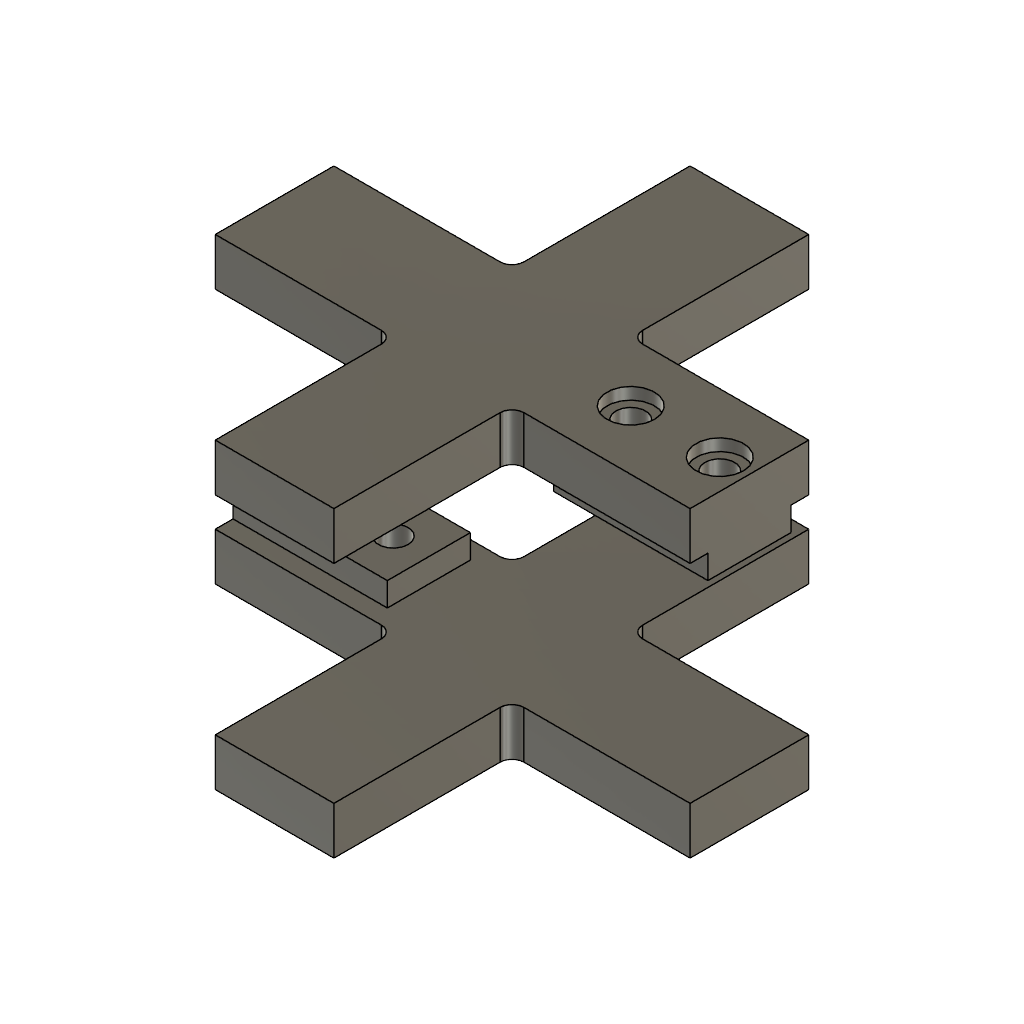
Sostegno_Sensore (Autodesk Fusion 360 design; units mm, degrees)
part number: 2026-10-16-15-58-05-429
Autodesk Fusion 360 part; units mm, degrees
sketch "Schizzo1" plane through (0, 0, 0) normal (0, 0, 1) x (1, 0, 0)
  line L0 (40, 10) -> (40, -10)
  line L1 (-40, -10) -> (-40, 10)
  line L2 (-10, 40) -> (10, 40)
  line L3 (10, -40) -> (-10, -40)
  line L4 (-10, -40) -> (-10, -12)
  line L5 (-10, 12) -> (-10, 40)
  line L6 (10, 40) -> (10, 12)
  line L7 (10, -12) -> (10, -40)
  line L8 (-40, 10) -> (-12, 10)
  line L9 (12, 10) -> (40, 10)
  line L10 (40, -10) -> (12, -10)
  line L11 (-12, -10) -> (-40, -10)
  arc A0 (-12, 10) -> (-10, 12) centre (-12, 12) ccw
  arc A1 (10, 12) -> (12, 10) centre (12, 12) ccw
  arc A2 (12, -10) -> (10, -12) centre (12, -12) ccw
  arc A3 (-10, -12) -> (-12, -10) centre (-12, -12) ccw
  constraint horizontal L8
  constraint vertical L0
  constraint horizontal L10
  constraint vertical L1
  constraint horizontal L2
  constraint vertical L6
  constraint horizontal L3
  constraint vertical L4
  constraint tangent L8 A0
  constraint tangent L5 A0
  constraint tangent L6 A1
  constraint tangent L9 A1
  constraint tangent L10 A2
  constraint tangent L7 A2
  constraint tangent L4 A3
  constraint tangent L11 A3
extrude "Estrusione1" add sketch "Schizzo1" along normal blind 8 makes body 1
sketch "Schizzo2" plane through (0, 0, 8) normal (0, 0, 1) x (-1, 0, 0)
  line L0 (10, 12) -> (10, 40)
  line L1 (10, 40) -> (-10, 40)
  line L2 (-10, 40) -> (-10, 12)
  line L3 (-12, 10) -> (-40, 10)
  line L4 (-40, 10) -> (-40, -10)
  line L5 (-40, -10) -> (-12, -10)
  line L6 (-10, -12) -> (-10, -40)
  line L7 (-10, -40) -> (10, -40)
  line L8 (10, -40) -> (10, -12)
  line L9 (12, -10) -> (40, -10)
  line L10 (40, -10) -> (40, 10)
  line L11 (40, 10) -> (12, 10)
  line L12 (40, -7) -> (14, -7)
  line L13 (14, -7) -> (14, 7)
  line L14 (14, 7) -> (40, 7)
  line L15 (40, 7) -> (40, -7)
  circle A0 centre (20, 0) radius 2.5
  circle A1 centre (35, 0) radius 2.5
  arc A2 (-12, 10) -> (-10, 12) centre (-12, 12) ccw
  arc A3 (-10, -12) -> (-12, -10) centre (-12, -12) ccw
  arc A4 (12, -10) -> (10, -12) centre (12, -12) ccw
  arc A5 (10, 12) -> (12, 10) centre (12, 12) ccw
  constraint horizontal L12
  constraint vertical L13
  constraint horizontal L14
  constraint vertical L15
extrude "Estrusione2" add sketch "Schizzo2" along normal blind 4 contours L10 L12 L13 L14 L15 bodies 1
extrude "Estrusione3" cut 2 faces at (-34.8146, 0.564, 8) (-19.8146, -0.8124, 8) along direction (0, 0, -1) blind 8 on bodies 1 bodies 1
sketch "Schizzo3" plane through (0, 0, 0) normal (0, 0, -1) x (1, 0, 0)
  circle A0 centre (-35, 0) radius 2.5
  circle A1 centre (-20, 0) radius 2.5
  line L0 (-10, 40) -> (-10, 12)
  line L1 (-12, 10) -> (-40, 10)
  line L2 (-40, 10) -> (-40, -10)
  line L3 (-40, -10) -> (-12, -10)
  line L4 (-10, -12) -> (-10, -40)
  line L5 (-10, -40) -> (10, -40)
  line L6 (10, -40) -> (10, -12)
  line L7 (12, -10) -> (40, -10)
  line L8 (40, -10) -> (40, 10)
  line L9 (40, 10) -> (12, 10)
  line L10 (10, 12) -> (10, 40)
  line L11 (10, 40) -> (-10, 40)
  circle A2 centre (-35, 0) radius 4
  circle A3 centre (-20, 0) radius 4
  arc A4 (-12, 10) -> (-10, 12) centre (-12, 12) ccw
  arc A5 (-10, -12) -> (-12, -10) centre (-12, -12) ccw
  arc A6 (12, -10) -> (10, -12) centre (12, -12) ccw
  arc A7 (10, 12) -> (12, 10) centre (12, 12) ccw
  constraint concentric A0 A2
  constraint concentric A1 A3
extrude "Estrusione4" cut sketch "Schizzo3" against normal blind 2 contours A2 | A3 bodies 1
ref_plane "Piano di lavoro1" through (0, 0, 43) normal (0, 0, 1) x (1, 0, 0)
sketch "Schizzo4" plane through (0, 0, 43) normal (0, 0, 1) x (1, 0, 0)
  line L0 (40, 10) -> (40, -10)
  line L1 (-40, -10) -> (-40, 10)
  line L2 (10, -40) -> (-10, -40)
  line L3 (-10, 40) -> (10, 40)
  line L4 (-40, 10) -> (-12, 10)
  line L5 (12, 10) -> (40, 10)
  line L6 (40, -10) -> (12, -10)
  line L7 (-12, -10) -> (-40, -10)
  line L8 (10, 40) -> (10, 12)
  line L9 (10, -12) -> (10, -40)
  line L10 (-10, -40) -> (-10, -12)
  line L11 (-10, 12) -> (-10, 40)
  arc A0 (-12, 10) -> (-10, 12) centre (-12, 12) ccw
  arc A1 (10, 12) -> (12, 10) centre (12, 12) ccw
  arc A2 (12, -10) -> (10, -12) centre (12, -12) ccw
  arc A3 (-10, -12) -> (-12, -10) centre (-12, -12) ccw
  constraint horizontal L4
  constraint vertical L0
  constraint horizontal L6
  constraint vertical L1
  constraint horizontal L2
  constraint vertical L10
  constraint horizontal L3
  constraint vertical L8
  constraint tangent L4 A0
  constraint tangent L11 A0
  constraint tangent L8 A1
  constraint tangent L5 A1
  constraint tangent L6 A2
  constraint tangent L9 A2
  constraint tangent L7 A3
  constraint tangent L10 A3
extrude "Estrusione5" add sketch "Schizzo4" along normal blind 8 separate body makes body 2
sketch "Schizzo5" plane through (0, 0, 43) normal (0, 0, -1) x (1, 0, 0)
  circle A0 centre (35, 0) radius 2.5
  circle A1 centre (20, 0) radius 2.5
  line L0 (40, -7) -> (14, -7)
  line L1 (14, -7) -> (14, 7)
  line L2 (14, 7) -> (40, 7)
  line L3 (40, 7) -> (40, -7)
  line L4 (-10, 40) -> (-10, 12)
  arc A2 (-12, 10) -> (-10, 12) centre (-12, 12) ccw
  line L5 (-12, 10) -> (-40, 10)
  line L6 (-40, 10) -> (-40, -10)
  line L7 (-40, -10) -> (-12, -10)
  arc A3 (-10, -12) -> (-12, -10) centre (-12, -12) ccw
  line L8 (-10, -12) -> (-10, -40)
  line L9 (-10, -40) -> (10, -40)
  line L10 (10, -40) -> (10, -12)
  arc A4 (12, -10) -> (10, -12) centre (12, -12) ccw
  line L11 (12, -10) -> (40, -10)
  line L12 (40, -10) -> (40, 10)
  line L13 (40, 10) -> (12, 10)
  arc A5 (10, 12) -> (12, 10) centre (12, 12) ccw
  line L14 (10, 12) -> (10, 40)
  line L15 (10, 40) -> (-10, 40)
  constraint horizontal L0
  constraint vertical L1
  constraint horizontal L2
  constraint vertical L3
extrude "Estrusione6" add sketch "Schizzo5" along normal blind 4 contours L0 L1 L2 L3 L12 bodies 2
extrude "Estrusione7" cut sketch "Schizzo5" against normal blind 8 contours A0 | A1 bodies 2
sketch "Schizzo6" plane through (0, 0, 51) normal (0, 0, 1) x (-1, 0, 0)
  circle A0 centre (-20, 0) radius 2.5
  circle A1 centre (-35, 0) radius 2.5
  circle A2 centre (-20, 0) radius 4
  circle A3 centre (-35, 0) radius 4
  line L0 (10, 12) -> (10, 40)
  line L1 (10, 40) -> (-10, 40)
  line L2 (-10, 40) -> (-10, 12)
  arc A4 (-12, 10) -> (-10, 12) centre (-12, 12) ccw
  line L3 (-12, 10) -> (-40, 10)
  line L4 (-40, 10) -> (-40, -10)
  line L5 (-40, -10) -> (-12, -10)
  arc A5 (-10, -12) -> (-12, -10) centre (-12, -12) ccw
  line L6 (-10, -12) -> (-10, -40)
  line L7 (-10, -40) -> (10, -40)
  line L8 (10, -40) -> (10, -12)
  arc A6 (12, -10) -> (10, -12) centre (12, -12) ccw
  line L9 (12, -10) -> (40, -10)
  line L10 (40, -10) -> (40, 10)
  line L11 (40, 10) -> (12, 10)
  arc A7 (10, 12) -> (12, 10) centre (12, 12) ccw
  constraint concentric A0 A2
  constraint concentric A1 A3
extrude "Estrusione8" cut sketch "Schizzo6" against normal blind 2 contours A2 | A3 bodies 2
named bodies: "Base", "Alto"
